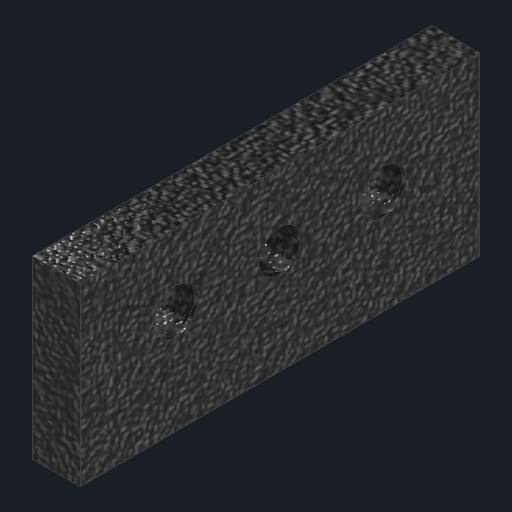
# Autodesk Inventor part: dec_worm_carrier
Saved by Autodesk Inventor 2027.1 (Build 311270010, 270A)
## iProperties
Created: 2026-11-04
Part Number: dec_worm_carrier
Material: Generic
Description: Dec worm carrier strip: 2x M5 cap screws + M5 push grub (worm mesh adjust), from photo 173116
Document SubType Name: Modeling
Designer: Claude (from photos)
Density: 1 g/cm^3
Appearance: Black Cast
Author: alexg
Autodesk Inventor part; units mm, degrees
ref_plane "Work Plane1" through (134, 0, 0) normal (1, 0, 0) x (0, 1, 0)
sketch "Carrier strip sketch" plane through (134, 0, 0) normal (1, 0, 0) x (0, 1, 0)
  line L0 (80, -25) -> (102, -25)
  line L1 (102, -25) -> (102, 25)
  line L2 (102, 25) -> (80, 25)
  line L3 (80, 25) -> (80, -25)
  constraints: 8 end point, 2 parallel, 1 horizontal, 1 perpendicular
extrude "Carrier strip" add sketch "Carrier strip sketch" along normal blind 6
ref_plane "Work Plane2" through (134, 0, 0) normal (1, 0, 0) x (0, 1, 0)
sketch "Bolt head counterbores sketch" plane through (134, 0, 0) normal (1, 0, 0) x (0, 1, 0)
  circle A0 centre (93, 13) radius 4.6
  circle A1 centre (93, -13) radius 4.6
  constraints: 2 centre point
extrude "Bolt head counterbores" cut sketch "Bolt head counterbores sketch" along normal blind 5.5
ref_plane "Work Plane3" through (134, 0, 0) normal (1, 0, 0) x (0, 1, 0)
sketch "Grub pocket sketch" plane through (134, 0, 0) normal (1, 0, 0) x (0, 1, 0)
  circle A0 centre (93, 0) radius 3.5
  constraints: 1 centre point
extrude "Grub pocket" cut sketch "Grub pocket sketch" along normal blind 2
ref_plane "Work Plane4" through (134, 0, 0) normal (1, 0, 0) x (0, 1, 0)
sketch "Bolt clearance + grub holes sketch" plane through (134, 0, 0) normal (1, 0, 0) x (0, 1, 0)
  circle A0 centre (93, 13) radius 2.8
  circle A1 centre (93, -13) radius 2.8
  circle A2 centre (93, 0) radius 2.6
  constraints: 3 centre point
extrude "Bolt clearance + grub holes" cut sketch "Bolt clearance + grub holes sketch" along normal blind 6
body "Solid1"
